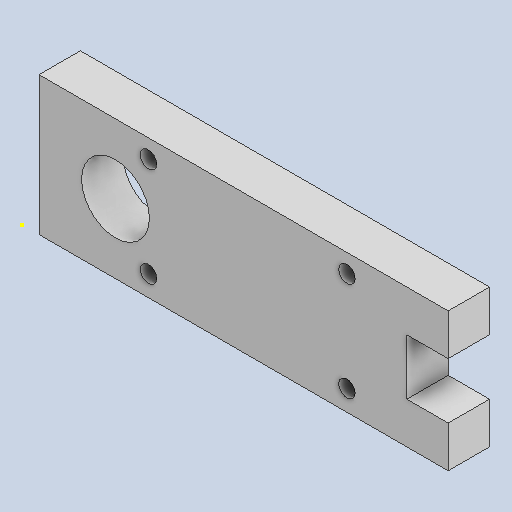
# Autodesk Inventor part: FrameBearing
Saved by Autodesk Inventor 2025.2 (Build 292293000, 293)
## iProperties
Created: 2025-06-22
Part Number: FrameBearing
Material: Generic
Document SubType Name: Modeling
Designer: ricoa
Density: 1 g/cm^3
Appearance: Default
Author: ricoa
Autodesk Inventor part; units mm, degrees
ref_plane "YZ Plane" through (0, 0, 0) normal (1, 0, 0) x (0, 1, 0)
ref_plane "XZ Plane" through (0, 0, 0) normal (0, 1, 0) x (-1, 0, 0)
ref_plane "XY Plane" through (0, 0, 0) normal (0, 0, 1) x (1, 0, 0)
sketch "Sketch1" plane through (0, 0, 0) normal (0, 0, 1) x (1, 0, 0)
  line L0 (2, 16.75) -> (2, 0) projected
  circle A0 centre (15.25, 2.5) radius 1 projected
  circle A1 centre (39.25, 2.5) radius 1 projected
  circle A2 centre (39.25, 14.5) radius 1 projected
  circle A3 centre (15.25, 14.5) radius 1 projected
  line L1 (2, 8.375) -> (11.25, 8.375)
  circle A4 centre (11.25, 8.375) radius 4.1
  line L2 (23.25, 16.75) -> (23.25, 0) construction
  line L3 (23.25, 8.375) -> (15.35, 8.375) construction
  line L4 (2, 0) -> (44.5, 0)
  line L5 (44.5, 16.75) -> (2, 16.75)
  line L6 (2, 16.75) -> (2, 0)
  line L7 (44.5, 0) -> (46.5, 0)
  line L8 (46.5, 0) -> (51.5, 0)
  line L9 (46.5, 0) -> (51.5, 0) construction
  line L10 (51.5, 16.75) -> (44.5, 16.75)
  line L11 (51.5, 0) -> (51.5, 5)
  line L12 (51.5, 5) -> (46.5, 5)
  line L13 (51.5, 16.75) -> (51.5, 11.75)
  line L14 (51.5, 11.75) -> (46.5, 11.75)
  line L15 (46.5, 5) -> (46.5, 11.75)
  line L16 (51.5, 0) -> (51.5, 5)
  line L17 (51.5, 11.75) -> (51.5, 16.75)
  dimension "d0" = 8.2
  dimension "d6" = 5
  dimension "d7" = 0
  dimension "d8" = 5
  dimension "d9" = 5
  constraints: 34 end point, 5 perpendicular, 3 horizontal, 2 collinear, 2 midpoint, 1 coincident, 1 horizontal alignment, 1 parallel, 1 vertical, 2 other
  measures "d6" distance of L7.end L8.end
  measures "d7" distance between parallel lines of L8 L9
  measures "d8" distance of L9.end L11.end
  measures "d9" distance of L10.start L13.end
extrude "Extrusion1" add sketch "Sketch1" along normal blind 5
sketch "Sketch2" plane through (0, 0, 5) normal (0, 0, 1) x (1, 0, 0)
  point P0 (0, 0)
body "Solid1"
